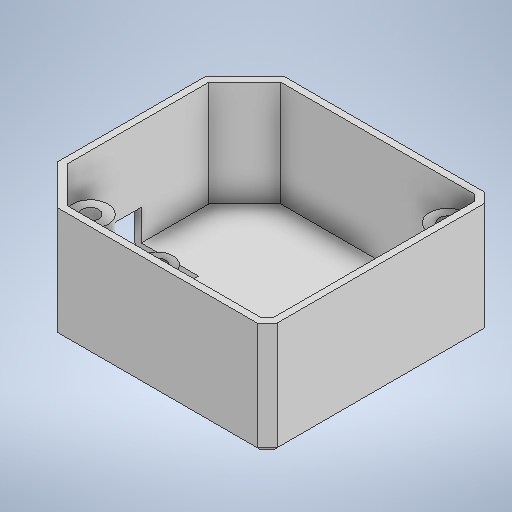
# Autodesk Inventor part: Socket
Saved by Autodesk Inventor 2025.2 (Build 292293000, 293)
## iProperties
Created: 2026-06-16
Part Number: Socket
Material: Generic
Document SubType Name: Modeling
Designer: Bruno
Density: 1 g/cm^3
Appearance: Default
Author: Bruno
## iProperties of the stored document Socket_3DPrint.ipt
Created: 2026-06-25
Part Number: Socket_3DPrint
Material: Generic
Document SubType Name: Modeling
Designer: Bruno
Density: 1 g/cm^3
Appearance: Default
Author: Bruno
Autodesk Inventor part; units mm, degrees
ref_plane "YZ Plane" through (0, 0, 0) normal (1, 0, 0) x (0, 1, 0)
ref_plane "XZ Plane" through (0, 0, 0) normal (0, 1, 0) x (-1, 0, 0)
ref_plane "XY Plane" through (0, 0, 0) normal (0, 0, 1) x (1, 0, 0)
sketch "Sketch1" plane through (0, 0, 0) normal (0, 1, 0) x (-1, 0, 0)
  line L0 (58.4, 33.4) -> (-58.4, 33.4) construction
  line L1 (-58.4, 33.4) -> (-58.4, -33.4)
  line L2 (-58.4, -33.4) -> (58.4, -33.4)
  line L3 (58.4, -33.4) -> (58.4, 33.4)
  line L4 (58.4, 33.4) -> (-58.4, -33.4) construction
  line L5 (-58.4, 33.4) -> (58.4, -33.4) construction
  line L6 (58.4, 33.4) -> (58.4, 88.4)
  line L7 (58.4, 88.4) -> (-58.4, 88.4)
  line L8 (-58.4, 88.4) -> (-58.4, 33.4)
  line L9 (20.8, 25.375) -> (-25.45, 25.375) construction
  line L10 (-25.45, 25.375) -> (-26.8, 24.025) construction
  line L11 (-26.8, 24.025) -> (-26.8, -24.025) construction
  line L12 (-26.8, -24.025) -> (-25.45, -25.375) construction
  line L13 (-25.45, -25.375) -> (20.8, -25.375) construction
  line L14 (20.8, -25.375) -> (26.8, -19.375) construction
  line L15 (26.8, -19.375) -> (26.8, 19.375) construction
  line L16 (26.8, 19.375) -> (20.8, 25.375) construction
  line L17 (0, 0) -> (14.4314, 0) construction
  line L18 (0, 0) -> (0, -12.5097) construction
  line L19 (20.8828, 25.575) -> (-25.5328, 25.575)
  line L20 (-25.5328, 25.575) -> (-27, 24.1078)
  line L21 (-27, 24.1078) -> (-27, -24.1078)
  line L22 (-27, -24.1078) -> (-25.5328, -25.575)
  line L23 (-25.5328, -25.575) -> (20.8828, -25.575)
  line L24 (20.8828, -25.575) -> (27, -19.4578)
  line L25 (27, -19.4578) -> (27, 19.4578) construction
  line L26 (27, 19.4578) -> (20.8828, 25.575)
  line L27 (29.5, -16.9578) -> (29.5, 16.9578)
  line L28 (27, -19.4578) -> (29.5, -16.9578)
  line L29 (27, 19.4578) -> (29.5, 16.9578)
  dimension "d0" = 116.8
  dimension "d1" = 66.8
  dimension "d2" = 121.8
  dimension "d6" = 50.75
  dimension "d7" = 53.6
  dimension "d8" = 50.75
  dimension "d9" = 53.6
  dimension "d10" = 45
  dimension "d11" = 48.05
  dimension "d12" = 38.75
  dimension "d13" = 0.2
  dimension "d19" = 2.7
  constraints: 60 end point, 10 perpendicular, 6 parallel, 3 equal length, 3 horizontal, 3 vertical, 2 midpoint, 1 collinear, 7 other
  measures "d0" distance of L1.end L2.end
  measures "d1" distance between parallel lines of L2 L0
  measures "d2" distance between parallel lines of L2 L7
  measures "d6" distance between parallel lines of L13 L9
  measures "d7" distance between parallel lines of L11 L15
  measures "d8" diameter of L9 L17
  measures "d9" diameter of L15 L18
  measures "d10" angle of L11 L12
  measures "d11" distance of L10.end L11.end
  measures "d12" distance of L14.end L15.end
  measures "d13" distance between parallel lines of L16 L26
  measures "d19" distance between parallel lines of L15 L27
extrude "Extrusion1" add sketch "Sketch1" along normal blind 1.6
sketch "Sketch2" plane through (0, 0, 0) normal (0, -1, 0) x (1, 0, 0)
  line L0 (58.4, -33.4) -> (-58.4, -33.4) projected
  line L1 (58.4, 88.4) -> (58.4, -33.4) projected
  line L2 (-58.4, 88.4) -> (58.4, 88.4) projected
  line L3 (-58.4, -33.4) -> (-58.4, 88.4) projected
  line L4 (27, -24.1078) -> (27, 24.1078) projected
  line L5 (27, 24.1078) -> (25.5328, 25.575) projected
  line L6 (25.5328, 25.575) -> (-20.8828, 25.575) projected
  line L7 (-20.8828, 25.575) -> (-29.5, 16.9578) projected
  line L8 (-29.5, 16.9578) -> (-29.5, -16.9578) projected
  line L9 (-29.5, -16.9578) -> (-20.8828, -25.575) projected
  line L10 (-20.8828, -25.575) -> (25.5328, -25.575) projected
  line L11 (25.5328, -25.575) -> (27, -24.1078) projected
  line L12 (28.6, 24.7706) -> (28.6, -24.7706)
  line L13 (28.6, -24.7706) -> (26.1956, -27.175)
  line L14 (26.1956, -27.175) -> (-21.5456, -27.175)
  line L15 (-21.5456, -27.175) -> (-31.1, -17.6206)
  line L16 (-31.1, -17.6206) -> (-31.1, 17.6206)
  line L17 (-31.1, 17.6206) -> (-21.5456, 27.175)
  line L18 (-21.5456, 27.175) -> (26.1956, 27.175)
  line L19 (26.1956, 27.175) -> (28.6, 24.7706)
  dimension "d86" = 1.6
  constraints: 16 end point, 7 other
  measures "d86" distance between parallel lines of L4 L12
extrude "Extrusion2" add sketch "Sketch2" along normal blind 25.235 contours L12 L13 L14 L15 L16 L17 L18 L19
sketch "Sketch3" plane through (0, -25.235, 0) normal (0, -1, 0) x (1, 0, 0)
  line L0 (26.1956, 27.175) -> (-21.5456, 27.175) projected
  line L1 (-21.5456, 27.175) -> (-31.1, 17.6206) projected
  line L2 (-31.1, 17.6206) -> (-31.1, -17.6206) projected
  line L3 (-31.1, -17.6206) -> (-21.5456, -27.175) projected
  line L4 (-21.5456, -27.175) -> (26.1956, -27.175) projected
  line L5 (26.1956, -27.175) -> (28.6, -24.7706) projected
  line L6 (28.6, -24.7706) -> (28.6, 24.7706) projected
  line L7 (28.6, 24.7706) -> (26.1956, 27.175) projected
  line L8 (27, -24.1078) -> (25.5328, -25.575) projected
  line L9 (25.5328, -25.575) -> (-20.8828, -25.575) projected
  line L10 (-20.8828, -25.575) -> (-29.5, -16.9578) projected
  line L11 (-29.5, -16.9578) -> (-29.5, 16.9578) projected
  line L12 (-29.5, 16.9578) -> (-20.8828, 25.575) projected
  line L13 (-20.8828, 25.575) -> (25.5328, 25.575) projected
  line L14 (25.5328, 25.575) -> (27, 24.1078) projected
  line L15 (27, 24.1078) -> (27, -24.1078) projected
  point P0 (0, 0)
extrude "Extrusion3" add sketch "Sketch3" along normal blind 1.6 contours L7 L6 L5 L4 L3 L2 L1 L0 | L8 L9 L10 L11 L12 L13 L14 L15
sketch "Sketch4" plane through (0, -26.835, 0) normal (0, -1, 0) x (1, 0, 0)
  line L0 (-31.1, 14.875) -> (-15.8, 14.875)
  line L1 (-15.8, 14.875) -> (-15.8, -0.775)
  line L2 (-15.8, -0.775) -> (-31.1, -0.775)
  line L3 (-20.8828, 25.575) -> (25.5328, 25.575) projected
  line L4 (25.5328, 25.575) -> (27, 24.1078) projected
  line L5 (27, 24.1078) -> (27, -24.1078) projected
  line L6 (27, -24.1078) -> (25.5328, -25.575) projected
  line L7 (25.5328, -25.575) -> (-20.8828, -25.575) projected
  line L8 (-20.8828, -25.575) -> (-29.5, -16.9578) projected
  line L9 (-29.5, -16.9578) -> (-29.5, 16.9578) projected
  line L10 (-29.5, 16.9578) -> (-20.8828, 25.575) projected
  line L11 (-21.5456, 27.175) -> (-31.1, 17.6206) projected
  line L12 (-31.1, 17.6206) -> (-31.1, -17.6206) projected
  line L13 (-31.1, -17.6206) -> (-21.5456, -27.175) projected
  line L14 (-21.5456, -27.175) -> (26.1956, -27.175) projected
  line L15 (26.1956, -27.175) -> (28.6, -24.7706) projected
  line L16 (28.6, -24.7706) -> (28.6, 24.7706) projected
  line L17 (28.6, 24.7706) -> (26.1956, 27.175) projected
  line L18 (26.1956, 27.175) -> (-21.5456, 27.175) projected
  point P0 (0, 0)
  dimension "d87" = 10.7
  dimension "d88" = 24.8
  dimension "d89" = 15.3
  constraints: 6 end point, 1 horizontal, 1 perpendicular
  measures "d87" distance between parallel lines of L3 L0
  measures "d88" distance between parallel lines of L7 L2
  measures "d89" distance between parallel lines of L12 L1
extrude "Extrusion4" cut sketch "Sketch4" against normal blind 9 contours L0 L9 L2 L12 | L0 L1 L2 L9
sketch "Sketch5" plane through (0, -25.235, 0) normal (0, 1, 0) x (1, 0, 0)
  line L0 (-29.5, -16.9578) -> (-29.5, 16.9578) projected
  line L1 (-29.5, 16.9578) -> (-20.8828, 25.575) projected
  line L2 (-20.8828, -25.575) -> (-29.5, -16.9578) projected
  line L3 (25.5328, -25.575) -> (-20.8828, -25.575) projected
  line L4 (27, -24.1078) -> (25.5328, -25.575) projected
  line L5 (27, 24.1078) -> (27, -24.1078) projected
  line L6 (25.5328, 25.575) -> (27, 24.1078) projected
  line L7 (-20.8828, 25.575) -> (25.5328, 25.575) projected
  line L8 (-29.3, 16.875) -> (-29.3, -16.875) construction
  line L9 (-29.3, -16.875) -> (-20.8, -25.375) construction
  line L10 (-20.8, -25.375) -> (25.45, -25.375) construction
  line L11 (25.45, -25.375) -> (26.8, -24.025) construction
  line L12 (26.8, -24.025) -> (26.8, 24.025) construction
  line L13 (26.8, 24.025) -> (25.45, 25.375) construction
  line L14 (25.45, 25.375) -> (-20.8, 25.375) construction
  line L15 (-20.8, 25.375) -> (-29.3, 16.875) construction
  circle A0 centre (22.95, 21.625) radius 4.25
  circle A1 centre (22.95, 21.625) radius 2
  circle A2 centre (-3.05, -21.875) radius 3.8
  circle A3 centre (-3.05, -21.875) radius 2
  circle A4 centre (-21.55, -19.375) radius 4.25
  circle A5 centre (-21.55, -19.375) radius 2
  point P0 (0, 0)
  point P1 (-29.5, -16.8164)
  point P2 (-29.5, 16.8164)
  point P3 (21.3816, 25.575)
  point P4 (27, 20.3366)
  point P5 (-2.184, -25.575)
  point P6 (-3.916, -25.575)
  point P7 (-23.1425, -23.3154)
  point P8 (-25.4904, -20.9675)
  dimension "d28" = 0.2
  dimension "d30" = 4
  dimension "d31" = 3.85
  dimension "d34" = 4
  dimension "d37" = 26
  dimension "d39" = 4
  dimension "d41" = 18.5
  dimension "d43" = 3.75
  dimension "d44" = 3.5
  dimension "d45" = 6
  dimension "d46" = 7.6
  dimension "d47" = 8.5
  dimension "d48" = 8.5
  constraints: 16 end point, 6 centre point, 3 coincident, 9 other
  measures "d28" distance between parallel lines of L0 L8
  measures "d30" diameter of A1
  measures "d31" distance from line of A0.centre L12
  measures "d34" diameter of A3
  measures "d37" horizontal distance of A0.centre A2.centre
  measures "d39" diameter of A5
  measures "d41" horizontal distance of A3.centre A4.centre
  measures "d43" distance from line of L14 A0.centre
  measures "d44" distance from line of L10 A2.centre
  measures "d45" distance from line of L10 A4.centre
  measures "d46" diameter of A2
  measures "d47" diameter of A0
  measures "d48" diameter of A4
extrude "Extrusion5" add sketch "Sketch5" along normal blind 20.015 contours A4 L2 | L7 A0 L5 | L7 L6 L5 A0 | A2 L3 picked at (-23.8933, -21.6613) picked at (-2.9696, -25.0035)
sketch "Sketch6" plane through (0, -25.235, 0) normal (0, 1, 0) x (1, 0, 0)
  circle A0 centre (-21.55, -19.375) radius 2 projected
  circle A1 centre (-3.05, -21.875) radius 2 projected
  circle A2 centre (22.95, 21.625) radius 2 projected
  point P0 (0, 0)
extrude "Extrusion6" add sketch "Sketch6" along normal blind 13.315
sketch "Sketch7" plane through (0, 1.6, 0) normal (0, 1, 0) x (1, 0, 0)
  line L0 (-58.4, 33.4) -> (-58.4, -88.4) projected
  line L1 (-58.4, -88.4) -> (58.4, -88.4) projected
  line L2 (58.4, -88.4) -> (58.4, 33.4) projected
  line L3 (58.4, 33.4) -> (-58.4, 33.4) projected
  point P0 (0, 0)
extrude "Extrusion7" cut sketch "Sketch7" against normal up to surface (1.6 mm away)
chamfer "Chamfer1" distance 1 angle 45 12 edges at (-3.05, -25.235, 18.075) (-18.5448, -25.235, 16.3698) (20.0518, -25.235, -18.5165) (-31.1, -26.835, -9.1978) (-26.3228, -26.835, -22.3978) (2.325, -26.835, -27.175) (27.3978, -26.835, -25.9728) (28.6, -26.835, 0) (27.3978, -26.835, 25.9728) (2.325, -26.835, 27.175) (-26.3228, -26.835, 22.3978) (-31.1, -26.835, 16.2478)
chamfer "Chamfer2" distance 0.4 angle 45 3 edges at (-22.95, -26.835, 14.875) (-15.8, -26.835, 7.05) (-22.95, -26.835, -0.775)
equation "\"d3\" = topbot"
equation "\"d17\" = topbot"
equation "\"walls\" = 1.6"
equation "\"topbot\" = 1.6"
equation "\"insertsD\" = 4.6"
equation "\"d35\" = 4.6"
equation "\"d40\" = 4.6"
body "Solid1"
